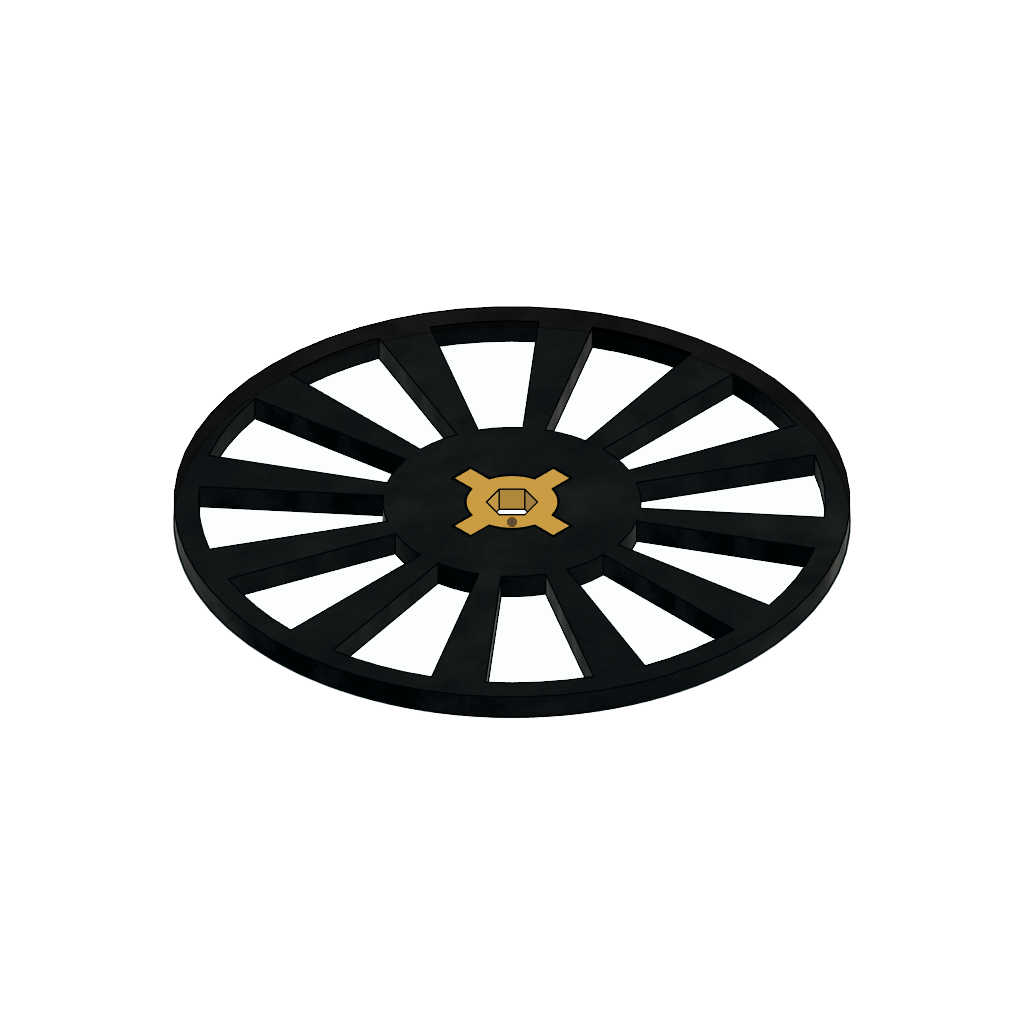
compliant wheel (Autodesk Fusion 360 design; units mm, degrees)
part number: 2026-10-20-00-30-21-507
part number: 2026-10-20-00-53-28-746
part number: 2026-10-20-00-57-08-657
Autodesk Fusion 360 part; units mm, degrees
note: some values were not read from the file. Set by a fixed rule: which face or edge a step refers to.
sketch "main cylinder" plane through (0, 0, 0) normal (0, 0, 1) x (1, 0, 0)
  circle A0 centre (0, 0) radius 55
  dimension "d1" = 110
  constraint coincident A0.centre origin
  measures "d1" diameter of A0
extrude "Extrude2" add sketch "main cylinder" along normal blind 4 makes body 1
sketch "compliant cutout" plane through (0, 0, 4) normal (0, 0, 1) x (-1, 0, 0)
  circle A0 centre (0, 0) radius 55
  circle A1 centre (0, 0) radius 55
  circle A2 centre (0, 0) radius 51
  circle A3 centre (0, 0) radius 16
  circle A4 centre (0, 0) radius 21
  line L0 (0.1129, -50.9999) -> (0.0465, -20.9999)
  line L1 (-17.3369, -47.9628) -> (-7.1387, -19.7494)
  dimension "d6" = -4
  dimension "d7" = 32
  dimension "d8" = 5
  dimension "d9" = 20
  constraint concentric A1 A3
  constraint coincident A2 L0.start
  constraint coincident A4 L0.end
  constraint perpendicular A4 L0
  constraint coincident A2 L1.start
  constraint coincident A4 L1.end
  constraint equal L0 L1
  measures "d7" diameter of A3
  measures "d9" angle of L0 L1
extrude "Extrude3" cut sketch "compliant cutout" against normal up to surface (4 mm away) contours A2 A4 L0 L1 picked at (-11.262, -39.3529) bodies 1
pattern_circular "C-Pattern1" count 12 over 360 about axis through (0, 0, 1.75) along (0, 0, 1) of "Extrude3"
copy_body "Body->Comp2" bodies 1 removing the originals makes body 2 in component "Compliant wheel"
sketch "Sketch1" plane through (0, 0, 4) normal (0, 0, 1) x (-1, 0, 0) in component "insert"
  line L0 (-10.4597, -18.2097) -> (-25.4021, -44.2236)
  arc A0 (-38.9956, -32.8686) -> (-25.4021, -44.2236) centre (0, 0) ccw
  line L1 (-38.9956, -32.8686) -> (-16.057, -13.5341)
  arc A1 (-16.057, -13.5341) -> (-10.4597, -18.2097) centre (0, 0) ccw
  line L2 (-18.1632, -10.5402) -> (-44.1107, -25.5977)
  arc A2 (-50.2055, -8.9672) -> (-44.1107, -25.5977) centre (0, 0) ccw
  line L3 (-50.2055, -8.9672) -> (-20.6728, -3.6924)
  arc A3 (-20.6728, -3.6924) -> (-18.1632, -10.5402) centre (0, 0) ccw
  line L4 (-20.9999, -0.0465) -> (-50.9999, -0.1129)
  arc A4 (-47.9628, 17.3369) -> (-50.9999, -0.1129) centre (0, 0) ccw
  line L5 (-47.9628, 17.3369) -> (-19.7494, 7.1387)
  arc A5 (-19.7494, 7.1387) -> (-20.9999, -0.0465) centre (0, 0) ccw
  line L6 (-18.2097, 10.4597) -> (-44.2236, 25.4021)
  arc A6 (-32.8686, 38.9956) -> (-44.2236, 25.4021) centre (0, 0) ccw
  line L7 (-32.8686, 38.9956) -> (-13.5341, 16.057)
  arc A7 (-13.5341, 16.057) -> (-18.2097, 10.4597) centre (0, 0) ccw
  line L8 (-10.5402, 18.1632) -> (-25.5977, 44.1107)
  arc A8 (-8.9672, 50.2055) -> (-25.5977, 44.1107) centre (0, 0) ccw
  line L9 (-8.9672, 50.2055) -> (-3.6924, 20.6728)
  arc A9 (-3.6924, 20.6728) -> (-10.5402, 18.1632) centre (0, 0) ccw
  line L10 (-0.0465, 20.9999) -> (-0.1129, 50.9999)
  arc A10 (17.3369, 47.9628) -> (-0.1129, 50.9999) centre (0, 0) ccw
  line L11 (17.3369, 47.9628) -> (7.1387, 19.7494)
  arc A11 (7.1387, 19.7494) -> (-0.0465, 20.9999) centre (0, 0) ccw
  line L12 (10.4597, 18.2097) -> (25.4021, 44.2236)
  arc A12 (38.9956, 32.8686) -> (25.4021, 44.2236) centre (0, 0) ccw
  line L13 (38.9956, 32.8686) -> (16.057, 13.5341)
  arc A13 (16.057, 13.5341) -> (10.4597, 18.2097) centre (0, 0) ccw
  line L14 (18.1632, 10.5402) -> (44.1107, 25.5977)
  arc A14 (50.2055, 8.9672) -> (44.1107, 25.5977) centre (0, 0) ccw
  line L15 (50.2055, 8.9672) -> (20.6728, 3.6924)
  arc A15 (20.6728, 3.6924) -> (18.1632, 10.5402) centre (0, 0) ccw
  line L16 (20.9999, 0.0465) -> (50.9999, 0.1129)
  arc A16 (47.9628, -17.3369) -> (50.9999, 0.1129) centre (0, 0) ccw
  line L17 (47.9628, -17.3369) -> (19.7494, -7.1387)
  arc A17 (19.7494, -7.1387) -> (20.9999, 0.0465) centre (0, 0) ccw
  line L18 (18.2097, -10.4597) -> (44.2236, -25.4021)
  arc A18 (32.8686, -38.9956) -> (44.2236, -25.4021) centre (0, 0) ccw
  line L19 (32.8686, -38.9956) -> (13.5341, -16.057)
  arc A19 (13.5341, -16.057) -> (18.2097, -10.4597) centre (0, 0) ccw
  line L20 (10.5402, -18.1632) -> (25.5977, -44.1107)
  arc A20 (8.9672, -50.2055) -> (25.5977, -44.1107) centre (0, 0) ccw
  line L21 (8.9672, -50.2055) -> (3.6924, -20.6728)
  arc A21 (3.6924, -20.6728) -> (10.5402, -18.1632) centre (0, 0) ccw
  line L22 (0.0465, -20.9999) -> (0.1129, -50.9999)
  arc A22 (-17.3369, -47.9628) -> (0.1129, -50.9999) centre (0, 0) ccw
  line L23 (-17.3369, -47.9628) -> (-7.1387, -19.7494)
  arc A23 (-7.1387, -19.7494) -> (0.0465, -20.9999) centre (0, 0) ccw
  circle A24 centre (0, 0) radius 55
  line L24 (-4.0153, 1.0759) -> (-2.9394, -2.9394)
  line L25 (-2.9394, -2.9394) -> (1.0759, -4.0153)
  line L26 (1.0759, -4.0153) -> (4.0153, -1.0759)
  line L27 (4.0153, -1.0759) -> (2.9394, 2.9394)
  line L28 (2.9394, 2.9394) -> (-1.0759, 4.0153)
  line L29 (-1.0759, 4.0153) -> (-4.0153, 1.0759)
  circle A25 centre (0, 0) radius 7.5
  line L30 (0, -7.5) -> (0, -11.5) construction
  line L31 (0, -11.5) -> (-2, -11.5)
  line L32 (-2, -11.5) -> (-2, -7.2284)
  line L33 (0, -11.5) -> (2, -11.5)
  line L34 (2, -11.5) -> (2, -7.2284)
  dimension "d14" = 3.6
  dimension "d15" = 15
  dimension "d16" = 4
  dimension "d17" = 2
  constraint coincident A0.centre A1.centre
  constraint concentric A0 A25
  constraint coincident A25 L30.start
  constraint perpendicular A25 L30
  constraint perpendicular L30 L31
  constraint coincident A25 L32.end
  constraint perpendicular L31 L32
  constraint symmetric L31.start L30 L33.start
  constraint symmetric L30 L31.end L33.end
  constraint symmetric L30 L32.end L34.end
  measures "d14" distance of A0.centre L29
  measures "d15" diameter of A25
  measures "d16" distance of L30.start L30.end
  measures "d17" distance of L30.end L31.end
extrude "Extrude1" add sketch "Sketch1" against normal up to surface (4 mm away) separate body contours A25 makes body 3 in component "insert"
extrude "Extrude2'" add sketch "Sketch1" against normal up to surface (4 mm away) separate body contours A25 L31 L32 L33 L34 makes body 4 in component "insert"
pattern_circular "C-Pattern1'" count 4 over 360 about axis through (0, 0, 4) along (0, 0, 1) of "Extrude2'" makes body 5 at (-10.0761, -2, 2.6667) makes body 6 at (2, -10.0761, 2.6667) makes body 7 at (10.0761, -2, 2.6667) in component "insert"
combine "Combine1" operation add target body 3 tool bodies 7 4 6 5 in component "insert"
combine "Combine1'" operation cut target body 2 tool bodies 3 keep tools makes body 8 at (0, 0, 0) in component "Compliant wheel"
delete_body "RemoveBody1" bodies 8 in component "Compliant wheel"
move_face "OffsetFaces1" offset -0.2 15 faces at (-6.9976, 2.6989, 1.3333) (-2, 10.0761, 2.6667) (-10.0761, 2, 2.6667) (-11.5, -0.6667, 2.6667) (-10.0761, -2, 2.6667) (-5.9127, -4.6142, 1.3333) (-2, -10.0761, 2.6667) (-0.6667, -11.5, 2.6667) (7.1216, -2.3523, 1.3333) (10.0761, -2, 2.6667) (11.5, -0.6667, 2.6667) (10.0761, 2, 2.6667) (2.6989, 6.9976, 1.3333) (2, 10.0761, 2.6667) (0.6667, 11.5, 2.6667) on bodies 2 in component "Compliant wheel"
component "Compliant wheel" placed x (1, 0, 0) y (0, 1, 0) z (0, 0, 1) at (0, 0, 0)
component "insert" placed x (1, 0, 0) y (0, 1, 0) z (0, 0, 1) at (0, 0, 0)
equation "d14 = ( 7.2 / 2 ) * 1 mm"
